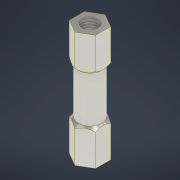
# Autodesk Inventor part: spacer 22mm silver
Saved by Autodesk Inventor 2021 (Build 250183000, 183)
## iProperties
Created: 2021-05-29
Part Number: spacer 22mm silver
Material: Aluminum 6061
Document SubType Name: Modeling
Designer: Galih Sukma Adjie
Density: 2.7 g/cm^3
Appearance: Silver
Author: Galih Sukma Adjie
Autodesk Inventor part; units mm, degrees
ref_plane "YZ Plane" through (0, 0, 0) normal (1, 0, 0) x (0, 1, 0)
ref_plane "XZ Plane" through (0, 0, 0) normal (0, 1, 0) x (-1, 0, 0)
ref_plane "XY Plane" through (0, 0, 0) normal (0, 0, 1) x (1, 0, 0)
sketch "Sketch2" plane through (0, 0, 0) normal (0, 1, 0) x (-1, 0, 0)
  circle A0 centre (0, 0) radius 2.25
  dimension "d2" = 4.5
  constraints: 1 centre point, 1 coincident
  measures "d2" diameter of A0
extrude "Extrusion1" add sketch "Sketch2" along normal mid plane 10
sketch "Sketch3" plane through (0, 5, 0) normal (0, 1, 0) x (1, 0, 0)
  line L0 (-2.5, 1.4434) -> (0, 2.8868)
  line L1 (0, 2.8868) -> (2.5, 1.4434)
  line L2 (2.5, 1.4434) -> (2.5, -1.4434)
  line L3 (2.5, -1.4434) -> (0, -2.8868)
  line L4 (0, -2.8868) -> (-2.5, -1.4434)
  line L5 (-2.5, -1.4434) -> (-2.5, 1.4434)
  point P0 (0, 0)
  point P1 (0, 0)
  dimension "d5" = 5
  constraints: 12 end point, 1 coincident, 13 other
  measures "d5" distance between parallel lines of L2 L5
extrude "Extrusion2" add sketch "Sketch3" along normal blind 6
sketch "Sketch4" plane through (0, -5, 0) normal (0, -1, 0) x (1, 0, 0)
  line L0 (-2.5, 1.4434) -> (0, 2.8868) projected
  line L1 (0, 2.8868) -> (2.5, 1.4434) projected
  line L2 (2.5, 1.4434) -> (2.5, -1.4434) projected
  line L3 (2.5, -1.4434) -> (0, -2.8868) projected
  line L4 (0, -2.8868) -> (-2.5, -1.4434) projected
  line L5 (-2.5, -1.4434) -> (-2.5, 1.4434) projected
  point P0 (0, 0)
extrude "Extrusion3" add sketch "Sketch4" along normal blind 6
chamfer "Chamfer1" distance 0.63 angle 45 2 edges at (2.25, -5, 0) (2.25, 5, 0)
sketch "Sketch5" plane through (0, 11, 0) normal (0, 1, 0) x (1, 0, 0)
  circle A0 centre (0, 0) radius 1.5
  dimension "d13" = 3
  constraints: 1 centre point, 1 coincident
  measures "d13" diameter of A0
extrude "Extrusion4" cut sketch "Sketch5" against normal through all
thread "Thread1" size "M3x0.5" class "6H" standard "ANSI Metric M Profile" full length
body "Solid1"
